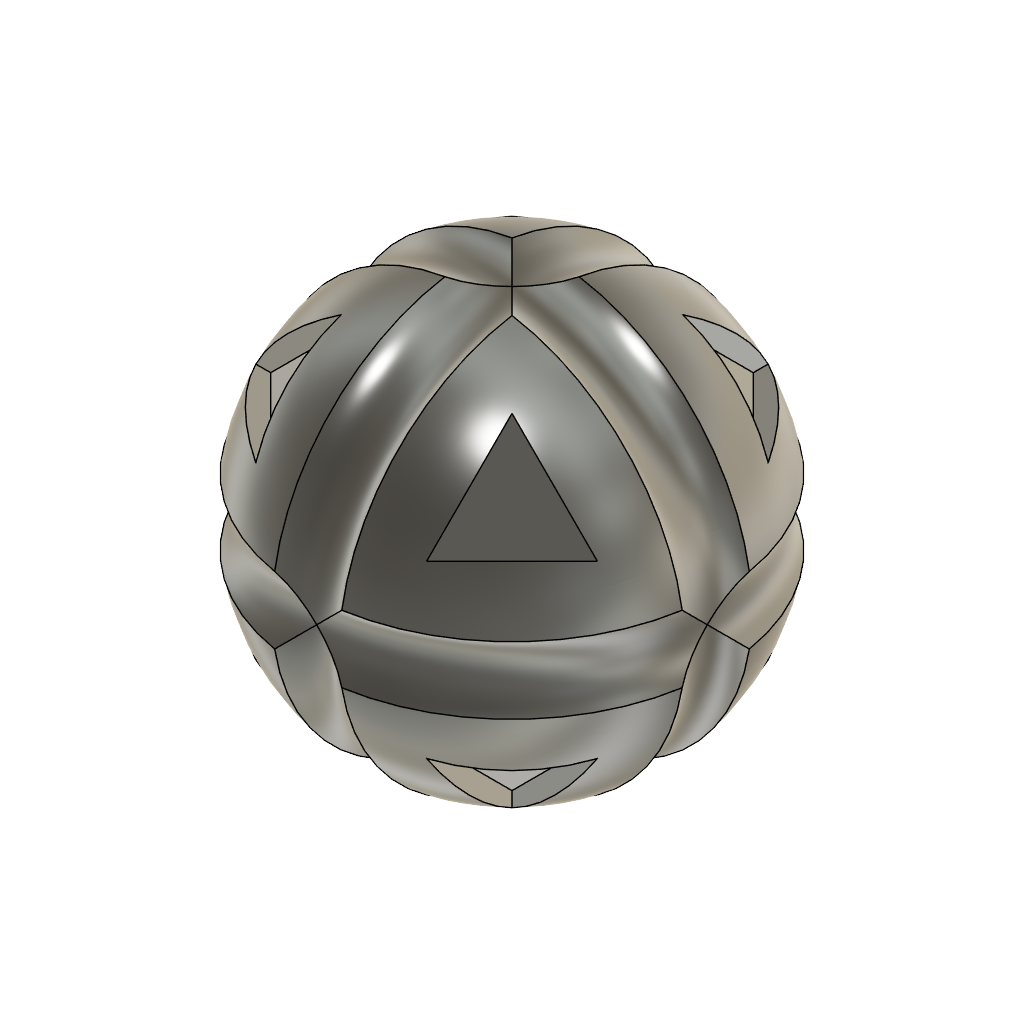
Marble ( Design 1 ) (Autodesk Fusion 360 design; units mm, degrees)
part number: 2026-10-18-19-34-22-836
Autodesk Fusion 360 part; units mm, degrees
sketch "Sketch1" plane through (0, 0, 0) normal (0, 1, 0) x (1, 0, 0)
  line L0 (0, -7.5) -> (0, 7.5)
  arc A0 (0, -7.5) -> (0, 7.5) centre (0, 0) ccw
  constraint coincident A0.centre origin
  constraint perpendicular L0 A0
revolve "Revolve1" add sketch "Sketch1" angle 360 about axis through (0, 0, 7.5) along (0, 0, -1) makes body 1
torus "TorusPrimitive3" cut centre line diameter 18 section diameter 4 placed x (1, 0, 0) y (0, 1, 0) z (0, 0, 1) at (0, 0, 0) bodies 1
torus "TorusPrimitive4" cut centre line diameter 18 section diameter 4 placed x (0, 1, 0) y (0, 0, 1) z (1, 0, 0) at (0, 0, 0) bodies 1
torus "TorusPrimitive5" cut centre line diameter 18 section diameter 4 placed x (1, 0, 0) y (0, 0, -1) z (0, 1, 0) at (0, 0, 0) bodies 1
ref_plane "WorkPlane2" through (1.2037, -1.2037, 7.3043) normal (0.57735, -0.57735, 0.57735) x (0.707107, 0.707107, 0)
sketch "Sketch9" plane through (3.2372, -3.2372, 3.2372) normal (0.57735, -0.57735, 0.57735) x (0.707107, 0.707107, 0)
  line L0 (2.1651, -1.25) -> (0, 2.5)
  line L1 (0, 2.5) -> (-2.1651, -1.25)
  line L2 (-2.1651, -1.25) -> (2.1651, -1.25)
  line L3 (0, 1.4289) -> (0, 18.3712)
  dimension "d22" = 1.25
  constraint perpendicular L2 L3
  measures "d22" distance of origin L2
extrude "Extrude2" add sketch "Sketch9" along normal blind 2 separate body makes body 2
pattern_circular "C-Pattern1" count 4 over 360 about axis through (0, 0, 1.75) along (0, 0, 1) of bodies 2 makes body 3 at (4.6427, 3.6221, 2.6015) makes body 4 at (-5.0276, 4.007, 2.9864) makes body 5 at (-4.6427, -3.6221, 2.6015)
pattern_circular "C-Pattern2" count 4 over 360 about axis through (1.75, 0, 0) along (1, 0, 0) of bodies 2 makes body 6 at (5.0276, -2.9864, -4.007) makes body 7 at (3.6221, 4.6427, -2.6015) makes body 8 at (3.6221, 2.6015, 4.6427)
pattern_circular "C-Pattern3" count 4 over 360 about axis through (1.75, 0, 0) along (1, 0, 0) of bodies 5 makes body 9 at (-5.0276, -2.9864, -4.007) makes body 10 at (-4.6427, 3.6221, -2.6015) makes body 11 at (-3.6221, 4.6427, 2.6015)
extrude "Extrude4" cut 1 faces at (-4.3919, -4.3919, 4.3919) along direction (0.57735, 0.57735, -0.57735) blind 1 on bodies 5 bodies 1 5
extrude "Extrude5" cut 1 faces at (4.3919, -4.3919, 4.3919) along direction (-0.57735, 0.57735, -0.57735) blind 1 on bodies 2 bodies 1 2
extrude "Extrude6" cut 1 faces at (4.3919, 4.3919, 4.3919) along direction (-0.57735, -0.57735, -0.57735) blind 1 on bodies 8 bodies 1 3 8
extrude "Extrude7" cut 1 faces at (-4.3919, 4.3919, 4.3919) along direction (0.57735, -0.57735, -0.57735) blind 1 on bodies 11 bodies 1 4 11
extrude "Extrude8" cut 1 faces at (4.3919, 4.3919, -4.3919) along direction (-0.57735, -0.57735, 0.57735) blind 1 on bodies 7 bodies 1 7
extrude "Extrude9" cut 1 faces at (4.3919, -4.3919, -4.3919) along direction (-0.57735, 0.57735, 0.57735) blind 1 on bodies 6 bodies 1 6
extrude "Extrude10" cut 1 faces at (-4.3919, -4.3919, -4.3919) along direction (0.57735, 0.57735, 0.57735) blind 1 on bodies 9 bodies 1 9
extrude "Extrude11" cut 1 faces at (-4.3919, 4.3919, -4.3919) along direction (0.57735, -0.57735, 0.57735) blind 1 on bodies 10 bodies 1 10
combine "Combine1" operation add target body 1 tool bodies 2 3 4 5 6 7 8 9 10 11
